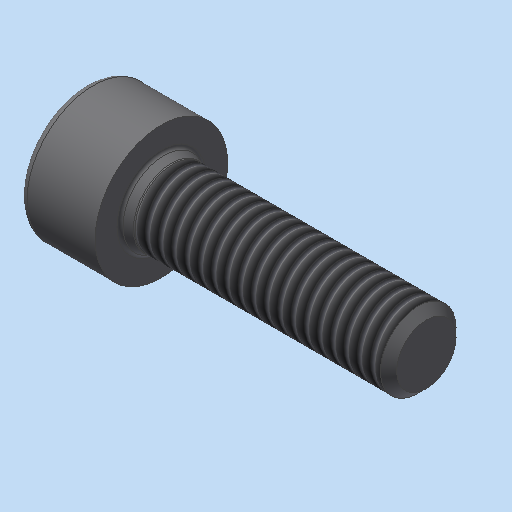
# Autodesk Inventor part: Zylinderschraube_ISO_4762___M4x14
Saved by Autodesk Inventor 2023.3 (Build 273359000, 359)
## iProperties
Shininess: 64.0
Length Units: 11269
Angle Units: 11279
Time Units: 11290
Mass Units: 11283
Length Display Precision: 3
Angle Display Precision: 2
Compacted: True
Part Number: Zylinderschraube_ISO_4762___M4x14
Document SubType Name: Modeling
Created: 2004-04-03
Material: xStahl_AnP_Dummymaterial
Description: =<RBPARTNOTITLE2>
Vendor: NORM8
Designer: S.Riedelsheimer
Manufacturer: Standard
Standards Organization: Custom
Density: 7.85 g/cm^3
Appearance: Stahl - normal AnP
Mass: 2.40559 g
Surface Area: 3.5849 cm^2
Volume: 0.306444 cm^3
DOC_ID: 5 F45 Zylinderschraube_ISO_4762___M4x16
GAIN_REFID: 20__Zylinderschraube_ISO_4762___M4x16:A9564
Control State: 0
Master: False
Checked Out: False
CNS_NB: Zylinderschraube ISO 4762 - M4x16
CNS_NN: ISO 4762
CNS_NT: Zylinderschrauben mit Innensechskant
CNS_NBSYN: Zylinderschraube ISO 4762 - $NENN.
CNS_LINA: Zylinderschraube ISO 4762 - M4x16
CNS_D: 4.000
CNS_D3: 3.141
CNS_P: 0.700
CNS_L: 16.000
CNS_S: 3.000
CNS_HM: 16.000
CNS_DK: 7.000
CNS_DA: 4.700
CNS_DS: 4.000
CNS_E: 3.440
CNS_K: 4.000
CNS_R: 0.200
CNS_T: 2.000
CNS_V: 0.400
CNS_DW: 6.530
CNS_W: 1.400
CNS_LF: 0.600
CNS_LG: 2.100
CNS_FORM: 1.000
CNS_NENN: M4x16
CNS_KT: DUMMY
PSOL_IDENT_0: {C:\partsolutions8\data\23d-libs\bosch_bamberg\schrauben\zylinderschrauben\din_en_iso_4762.prj},170
PSOL_IDENT_1: {M=Nenngewinde},{VTYP=3D},{NB=Zylinderschraube ISO 4762 - M4x16},{NN=ISO 4762},{DATE=26.11.2003},{GE
PSOL_IDENT_2: OMDATE=26.11.2003},{VERSION=v2},{LINEID=410},{LINESUBID=-1},{WBVAR=}  {NB=Zylinderschraube ISO 4762
PSOL_IDENT_3: - M4x16},{LINA=Zylinderschraube ISO 4762 - M4x16},{KT=DUMMY},{IDNR=},{D=4.000},{D3=3.141},{P=0.700},
PSOL_IDENT_4: {L=16.000},{S=3.000},{HM=16.000},{DK=7.000},{DA=4.700},{DS=4.000},{E=3.440},{K=4.000},{R=0.200},{T=2
PSOL_IDENT_5: .000},{V=0.400},{DW=6.530},{W=1.400},{LF=0.600},{LG=2.100},{FORM=1.000},{NENN=M4x16}
Masse: 0,000 kg
Volumen: 331,577 mm^3
Fläche: 383,622 mm^2
DEF_STKID: T18527
Bezeichnung1: Zylinderschraube ISO 4762 - M4x16
Bezeichnung2: Zylinderschrauben mit Innensechskant
RBPARTNOTITLE2: Zylinderschrauben mit Innensechskant
RBPARTNOTITLE1: Hexagon socket head cap screws
AnP_Kategorie: 4
RBDRAWINGMISSINGSPEC: --
RBPARTMADEOF: ISO 4762 - M4x14 - 8.8 verzinkt
Density: 0.0
Volumn: 0.0
Area: 0.0
PropertySet Name: Model Information
Title: Zylinderschraube ISO 4762 - M4x14
Author: S.Riedelsheimer
Keywords: =<RBPARTMADEOF>
Comments: =<RBSURFACE2>
Revision Number: 01
Autodesk Inventor part; units mm, degrees
sketch "Skizze_2" plane through (0, 0, 0) normal (0, 0, 1) x (1, 0, 0)
  line L0 (19, 0) -> (-7, 0)
  line L1 (-0.534, 0) -> (-1.4, 1.5)
  line L2 (-1.4, 1.5) -> (-3.78, 1.5)
  line L3 (-3.78, 1.5) -> (-4, 1.72)
  line L4 (-4, 1.72) -> (-4, 3.1)
  arc A0 (-3.6, 3.5) -> (-4, 3.1) centre (-3.6, 3.1) ccw
  line L5 (-3.6, 3.5) -> (0, 3.5)
  line L6 (0, 3.5) -> (0, 2.35)
  arc A1 (0, 2.35) -> (0.1298, 2.1627) centre (0.2, 2.35) ccw
  line L7 (0.1298, 2.1627) -> (0.5298, 2.0127)
  arc A2 (0.5298, 2.0127) -> (0.6, 2) centre (0.6, 2.2) ccw
  line L8 (0.6, 2) -> (13.5705, 2)
  line L9 (13.5705, 2) -> (14, 1.5705)
  line L10 (14, 1.5705) -> (14, 0)
  line L11 (14, 0) -> (-0.534, 0)
  line L12 (0, 4.2994) -> (0, -0.7166) projected
  line L13 (-12.2, 0) -> (24.2, 0) projected
  dimension "d5" = 4
  dimension "d6" = 0.4
  dimension "d7" = 3.5
  dimension "d8" = 0.22
  dimension "d9" = 45
  dimension "d10" = 1.5
  dimension "d11" = 60
  dimension "d12" = 2.6
  dimension "d13" = 0.2
  dimension "d14" = 0.2
  dimension "d15" = 2
  dimension "d16" = 20.556
  dimension "d17" = 0.6
  dimension "d18" = 2.2
  dimension "d19" = 2.35
  dimension "d20" = 0.4295
  dimension "d21" = 45
  dimension "d22" = 14
  constraints: 24 end point, 6 point on circle, 6 tangent, 3 centre point, 2 collinear
  measures "d5" distance between parallel lines of L4 L12
  measures "d6" radius of A0
  measures "d7" distance between parallel lines of L0 L5
  measures "d8" distance from line of L2.end L4
  measures "d9" angle of L3 L4
  measures "d10" distance between parallel lines of L0 L2
  measures "d11" angle of L1 L2
  measures "d12" distance from line of L1.end L4
  measures "d13" radius of A1
  measures "d14" radius of A2
  measures "d15" distance between parallel lines of L11 L8
  measures "d16" angle of L7 L8
  measures "d17" distance from line of A2.centre L12
  measures "d18" distance from line of A2.centre L0
  measures "d19" distance from line of A1.centre L13
  measures "d20" distance from line of L8.end L10
  measures "d21" angle of L9 L8
  measures "d22" distance between parallel lines of L12 L10
revolve "Drehung1" add sketch "Skizze_2" angle 360 about axis through (19, 0, 0) along (1, 0, 0)
thread "Gewinde1" size "M4x0.7" class "6g" standard "ANSI Metric M Profile" length 13.9
sketch "Skizze_1" plane through (-1.4, 0, 0) normal (1, 0, 0) x (0, 0, -1)
  line L0 (-1.5, 0.866) -> (-1.5, -0.866)
  line L1 (-1.5, -0.866) -> (0, -1.7321)
  line L2 (0, -1.7321) -> (1.5, -0.866)
  line L3 (1.5, -0.866) -> (1.5, 0.866)
  line L4 (1.5, 0.866) -> (0, 1.7321)
  line L5 (0, 1.7321) -> (-1.5, 0.866)
  constraints: 12 end point
extrude "Extrusion1" cut sketch "Skizze_1" against normal blind 4
ref_plane "IP1_XY" through (0, 0, 0) normal (1, 0, 0) x (0, 0, -1)
ref_plane "IP1_YZ" through (0, 0, 0) normal (0, 0, -1) x (0, 1, 0)
ref_plane "IP3_XY" through (16, 0, 0) normal (1, 0, 0) x (0, 0, -1)
ref_plane "IP3_YZ" through (16, 0, 0) normal (0, 0, -1) x (0, 1, 0)
ref_plane "IP2_XY" through (-4, 0, 0) normal (1, 0, 0) x (0, 0, -1)
ref_plane "IP2_YZ" through (-4, 0, 0) normal (0, 0, -1) x (0, 1, 0)
